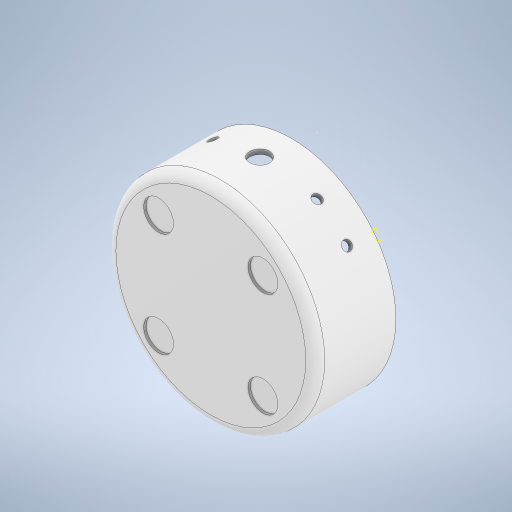
# Autodesk Inventor part: Основание
Saved by Autodesk Inventor 2024 (Build 280153000, 153)
## iProperties
Created: 2026-03-25
Part Number: Основание
Material: Типовые
Document SubType Name: Modeling
Designer: Pavel
Density: 1 g/cm^3
Appearance: По умолчанию
Author: Pavel
Autodesk Inventor part; units mm, degrees
ref_plane "РабПлоскость1" through (46.7801, -28.1809, 1.4774) normal (0.0000001, -1, 0) x (1, 0.0000001, 0.0000001)
ref_plane "РабПлоскость2" through (51.3477, 48.0491, 0.6174) normal (-0.0000001, 1, 0) x (-1, -0.0000001, 0)
sketch "Эскиз1" plane through (51.3477, 48.0491, 0.6174) normal (-0.0000001, 1, 0) x (-1, -0.0000001, 0)
  line L0 (0, 0) -> (2.8, 0) projected
  line L1 (0, -1.3) -> (0, 0) projected
  line L2 (2.8, -1.3) -> (0, -1.3) projected
  line L3 (2.8, 0) -> (2.8, -1.3) projected
  point P0 (51.3477, -0.6174)
sketch "Эскиз2" plane through (46.7801, -28.1809, 1.4774) normal (0.0000001, -1, 0) x (1, 0.0000001, 0.0000001)
  line L0 (6.3492, 0) -> (0, 0) projected
  arc A0 (7.4946, -1.2954) -> (6.3492, -0.15) centre (6.3492, -1.2954) ccw projected
  arc A1 (7.6446, -1.2954) -> (6.3492, 0) centre (6.3492, -1.2954) ccw projected
  arc A2 (6.3492, -3.16) -> (7.6446, -1.8646) centre (6.3492, -1.8646) ccw projected
  line L1 (7.6446, -1.8646) -> (7.6446, -1.2954) projected
  line L2 (2.6871, -3.16) -> (6.3492, -3.16) projected
  line L3 (0, -3.16) -> (2.6371, -3.16) projected
  arc A3 (-1.2954, -1.8646) -> (0, -3.16) centre (0, -1.8646) ccw projected
  arc A4 (0, 0) -> (-1.2954, -1.2954) centre (0, -1.2954) ccw projected
  line L4 (-1.2954, -1.2954) -> (-1.2954, -1.8646) projected
  line L5 (0, 0) -> (6.3492, 0)
  line L6 (6.3492, -3.16) -> (0, -3.16)
  arc A5 (-1.2954, -1.8646) -> (0, -3.16) centre (0, -1.8646) ccw
  arc A6 (0, 0) -> (-1.2954, -1.2954) centre (0, -1.2954) ccw
  arc A7 (7.6446, -1.2954) -> (6.3492, 0) centre (6.3492, -1.2954) ccw
  arc A8 (6.3492, -3.16) -> (7.6446, -1.8646) centre (6.3492, -1.8646) ccw
  line L7 (-1.2954, -1.2954) -> (-1.2954, -1.8646)
  line L8 (7.6446, -1.2954) -> (7.6446, -1.8646)
  arc A9 (7.6446, -1.2954) -> (6.3492, 0) centre (6.3492, -1.2954) ccw projected
  line L9 (7.6446, -1.8646) -> (7.6446, -1.2954) projected
  arc A10 (6.3492, -3.16) -> (7.6446, -1.8646) centre (6.3492, -1.8646) ccw projected
  line L10 (2.6871, -3.16) -> (6.3492, -3.16) projected
  line L11 (6.3492, 0) -> (0, 0) projected
  arc A11 (0, 0) -> (-1.2954, -1.2954) centre (0, -1.2954) ccw projected
  line L12 (-1.2954, -1.2954) -> (-1.2954, -1.8646) projected
  arc A12 (-1.2954, -1.8646) -> (0, -3.16) centre (0, -1.8646) ccw projected
  line L13 (0, -3.41) -> (6.3492, -3.41)
  arc A13 (6.3492, -3.41) -> (7.8946, -1.8646) centre (6.3492, -1.8646) ccw
  line L14 (7.8946, -1.8646) -> (7.8946, -1.2954)
  arc A14 (7.8946, -1.2954) -> (6.3492, 0.25) centre (6.3492, -1.2954) ccw
  line L15 (6.3492, 0.25) -> (0, 0.25)
  arc A15 (0, 0.25) -> (-1.5454, -1.2954) centre (0, -1.2954) ccw
  line L16 (-1.5454, -1.2954) -> (-1.5454, -1.8646)
  arc A16 (-1.5454, -1.8646) -> (0, -3.41) centre (0, -1.8646) ccw
  point P0 (-46.7801, -1.4774)
  dimension "d20" = 0.25
  constraints: 16 end point, 16 point on circle, 8 centre point, 4 coincident, 2 collinear, 2 parallel, 1 vertical, 7 other
  measures "d20" distance between parallel lines of L6 L13
ref_plane "РабПлоскость3" through (49.9497, 17.7991, -1.7826) normal (0, 0, 1) x (1, 0, 0)
ref_plane "РабПлоскость4" through (39.6247, 34.8888, -1.2881) normal (-0.5, 0.8660254, 0) x (-0.8660254, -0.5, 0)
ref_plane "РабПлоскость5" through (64.632, 43.9707, -1.7881) normal (0.5000001, 0.8660254, 0) x (-0.8660254, 0.5000001, 0)
sketch "Эскиз5" plane through (64.632, 43.9707, -1.7881) normal (0.5000001, 0.8660254, 0) x (-0.8660254, 0.5000001, 0)
  line L0 (-0.5, 1) -> (0, 1) projected
  line L1 (-1.25, 1) -> (-0.5, 1) projected
  line L2 (0, 1) -> (0.75, 1) projected
  circle A0 centre (-0.25, 0.5) radius 1
  point P0 (33.9877, 1.7881)
  constraints: 1 centre point, 1 coincident
ref_plane "РабПлоскость6" through (73.2116, 36.8036, -1.2881) normal (0.777146, 0.6293203, 0) x (-0.6293203, 0.777146, 0)
sketch "Эскиз6" plane through (73.2116, 36.8036, -1.2881) normal (0.777146, 0.6293203, 0) x (-0.6293203, 0.777146, 0)
  point P0 (17.4718, 1.2881)
ref_plane "РабПлоскость7" through (49.9497, 17.7991, -1.7826) normal (0, 0, 1) x (1, 0, 0)
sketch "Эскиз8" plane through (49.9497, 17.7991, -1.7826) normal (0, 0, 1) x (1, 0, 0)
  circle A0 centre (0, 0) radius 20 projected
  circle A1 centre (0, 0) radius 21
  circle A2 centre (0, 0) radius 22
  point P0 (-49.9497, -17.7991)
  dimension "d8" = 1
  dimension "d9" = 1
  constraints: 2 centre point
  measures "d8" radial gap between concentric circles of A0 A1
  measures "d9" radial gap between concentric circles of A1 A2
extrude "Выдавливание2" add sketch "Эскиз8" along normal blind 15 and the other way blind 5 contours A2
extrude "Выдавливание5" cut sketch "Эскиз1" against normal blind 15
extrude "Выдавливание7" cut sketch "Эскиз2" against normal blind 30 contours A1 L1 A2 L2 L6 L3 A3 L4 A4 L0 | A16 L16 A15 L15 A14 L14 A13 L13
sketch "Эскиз9" plane through (49.9497, 17.7991, 13.2174) normal (0, 0, 1) x (1, 0, 0)
  circle A0 centre (0, 0) radius 20 projected
  circle A1 centre (0, 0) radius 21 projected
  point P0 (-49.9497, -17.7991)
extrude "Выдавливание8" add sketch "Эскиз9" against normal blind 11
ref_plane "РабПлоскость8" through (49.9497, 17.7991, -1.7826) normal (0, 0, 1) x (1, 0, 0)
sketch "Эскиз10" plane through (49.9497, 17.7991, -1.7826) normal (0, 0, 1) x (1, 0, 0)
  circle A0 centre (-14, 11) radius 1 projected
  circle A1 centre (15, -9) radius 1 projected
  circle A2 centre (0, 0) radius 20 projected
  line L0 (16, -7.3333) -> (18.0687, -8.5745)
  line L1 (14, -10.6667) -> (16.0687, -11.9079)
  arc A3 (16, -7.3333) -> (14, -10.6667) centre (15, -9) ccw
  line L2 (15.8575, -9.5145) -> (14.4855, -9.8575)
  line L3 (14.4855, -9.8575) -> (14.1425, -8.4855)
  line L4 (14.1425, -8.4855) -> (15.5145, -8.1425)
  line L5 (15.5145, -8.1425) -> (15.8575, -9.5145)
  arc A4 (16.0687, -11.9079) -> (18.0687, -8.5745) centre (0, 0) ccw
  line L6 (-14, 11) -> (-15.7264, 12.3564)
  line L7 (-14.7863, 11.6178) -> (-13.3822, 11.7863)
  line L8 (-13.3822, 11.7863) -> (-13.2137, 10.3822)
  line L9 (-13.2137, 10.3822) -> (-14.6178, 10.2137)
  line L10 (-14.6178, 10.2137) -> (-14.7863, 11.6178)
  line L11 (-15.3956, 9.5409) -> (-16.8883, 10.7137)
  line L12 (-12.7644, 12.5726) -> (-14.4119, 13.8671)
  arc A5 (-15.3956, 9.5409) -> (-12.7644, 12.5726) centre (-14.154, 11.121) ccw
  arc A6 (-14.4119, 13.8671) -> (-16.8883, 10.7137) centre (0, 0) ccw
  line L13 (15, -9) -> (17.1499, -10.2899)
  line L14 (15, -9) -> (16.029, -7.285)
  line L15 (15, -9) -> (13.971, -10.715)
  arc A7 (16.0687, -11.9079) -> (18.0687, -8.5745) centre (0, 0) ccw
  point P0 (-49.9497, -17.7991)
  dimension "d31" = 2.0096
  dimension "d32" = 2
  dimension "d33" = 2
  constraints: 32 end point, 16 point on circle, 6 coincident, 5 centre point, 4 parallel, 2 line through centre, 2 perpendicular, 2 point on line, 13 other
  measures "d31" radius of A5
  measures "d32" distance of L13.start L14.end
  measures "d33" distance of L13.start L15.end
extrude "Выдавливание9" add sketch "Эскиз10" along normal up to surface (15 mm away) contours A0 L8 | L7 A0 | A0 L9 | L10 A0 | A1 L5 | A1 L14 L0 A2 L13 | L4 A1 | A1 L15 A3 L14 | L13 A2 L1 L15 A1 | A1 L2 | L3 A1 | A2 L12 A5 L11
sketch "Эскиз11" plane through (51.3477, 48.0491, 0.6174) normal (-0.0000001, 1, 0) x (-1, -0.0000001, 0)
  line L0 (2.8, -1.3) -> (2.8, 0) projected
  line L1 (0, 0) -> (2.8, 0) projected
  line L2 (2.8, -1.3) -> (0, 0)
  line L3 (2.8, 0) -> (0, -1.3)
  circle A0 centre (1.4, -0.65) radius 2.1
  point P0 (51.3477, -0.6174)
  dimension "d36" = 4.2
  constraints: 4 end point, 1 centre point, 1 midpoint
  measures "d36" diameter of A0
extrude "Выдавливание10" cut sketch "Эскиз11" against normal blind 10
sketch "Эскиз12" plane through (73.2116, 36.8036, -1.2881) normal (0.777146, 0.6293203, 0) x (-0.6293203, 0.777146, 0)
  circle A0 centre (-0.25, 0) radius 1
  point P0 (17.4718, 1.2881)
  constraints: 1 centre point
sketch "Эскиз14" plane through (49.9497, 17.7991, 13.2174) normal (0, 0, 1) x (1, 0, 0)
  circle A0 centre (0, 0) radius 22 projected
  point P0 (-49.9497, -17.7991)
extrude "Выдавливание12" cut sketch "Эскиз14" against normal blind 5
sketch "Эскиз15" plane through (49.9497, 17.7991, 2.2174) normal (0, 0, -1) x (-1, 0, 0)
  arc A0 (-16.0687, -11.9079) -> (16.8883, 10.7137) centre (0, 0) ccw projected
  line L0 (16.8883, 10.7137) -> (17.6785, 11.3346)
  circle A1 centre (0, 0) radius 21 projected
  arc A2 (14.4119, 13.8671) -> (-18.0687, -8.5745) centre (0, 0) ccw projected
  line L1 (14.4119, 13.8671) -> (15.202, 14.4879)
  line L2 (14.7863, 11.6178) -> (13.3822, 11.7863) projected
  line L3 (16.8883, 10.7137) -> (15.3956, 9.5409) projected
  arc A3 (16.8883, 10.7137) -> (14.4119, 13.8671) centre (0, 0) ccw projected
  arc A4 (16.8883, 10.7137) -> (14.4293, 13.849) centre (0, 0) ccw
  line L4 (-15.5145, -8.1425) -> (-15.8575, -9.5145) projected
  line L5 (-18.0687, -8.5745) -> (-18.9301, -9.0914)
  line L6 (-16.0687, -11.9079) -> (-16.9301, -12.4247)
  arc A5 (-18.0687, -8.5745) -> (-16.0687, -11.9079) centre (0, 0) ccw
  arc A6 (-18.9301, -9.0914) -> (-16.9301, -12.4247) centre (0, 0) ccw
  arc A7 (17.6785, 11.3346) -> (15.202, 14.4879) centre (0, 0) ccw
  point P0 (49.9497, -17.7991)
  constraints: 13 point on circle, 8 end point, 4 centre point, 4 coincident
extrude "Выдавливание13" add sketch "Эскиз15" along normal up to surface (4 mm away) contours L6 A1 L5 A5 | A3 L1 A1 L0
sketch "Эскиз16" plane through (49.9497, 17.7991, 8.2174) normal (0, 0, 1) x (1, 0, 0)
  circle A0 centre (0, 0) radius 22 projected
  point P0 (-49.9497, -17.7991)
extrude "Выдавливание14" add sketch "Эскиз16" along normal blind 2
fillet "Сопряжение2" radius 2 1 edges at (27.9497, 17.7991, 10.2174)
extrude "Выдавливание15" cut sketch "Эскиз12" against normal up to surface (10 mm away)
extrude "Выдавливание16" cut sketch "Эскиз5" against normal blind 10
ref_plane "РабПлоскость9" through (36.4497, 40.388, -1.2881) normal (-0.5, 0.8660254, 0) x (-0.8660254, -0.5, 0)
sketch "Эскиз17" plane through (36.4497, 40.388, -1.2881) normal (-0.5, 0.8660254, 0) x (-0.8660254, -0.5, 0)
  line L0 (-0.5, 0.5) -> (0, 0.5) projected
  circle A0 centre (-0.3141, 0.0002) radius 1
  point P0 (51.7604, 1.2881)
  constraints: 1 centre point
extrude "Выдавливание17" cut sketch "Эскиз17" against normal blind 10
sketch "Эскиз20" plane through (49.9497, 17.7991, -1.7826) normal (0, 0, -1) x (-1, 0, 0)
  line L0 (13.2137, 10.3822) -> (14.6178, 10.2137) projected
  line L1 (14.6178, 10.2137) -> (14.7863, 11.6178) projected
  line L2 (14.7863, 11.6178) -> (13.3822, 11.7863) projected
  line L3 (13.3822, 11.7863) -> (13.2137, 10.3822) projected
  line L4 (-14.4855, -9.8575) -> (-14.1425, -8.4855) projected
  line L5 (-14.1425, -8.4855) -> (-15.5145, -8.1425) projected
  line L6 (-15.5145, -8.1425) -> (-15.8575, -9.5145) projected
  line L7 (-15.8575, -9.5145) -> (-14.4855, -9.8575) projected
  point P0 (49.9497, -17.7991)
extrude "Выдавливание19" add sketch "Эскиз20" against normal blind 10
sketch "Эскиз21" plane through (49.9497, 17.7991, -1.7826) normal (0, 0, -1) x (-1, 0, 0)
  arc A0 (12.7644, 12.5726) -> (15.3956, 9.5409) centre (14.154, 11.121) ccw projected
  circle A1 centre (14.154, 11.121) radius 0.9
  arc A2 (-14, -10.6667) -> (-16, -7.3333) centre (-15, -9) ccw projected
  circle A3 centre (-15, -9) radius 0.9
  point P0 (49.9497, -17.7991)
  dimension "d62" = 1.8
  dimension "d63" = 1.8
  constraints: 2 centre point, 2 coincident
  measures "d62" diameter of A1
  measures "d63" diameter of A3
extrude "Выдавливание20" cut sketch "Эскиз21" against normal blind 10 contours A3
sketch "Эскиз22" plane through (49.9497, 17.7991, 10.2174) normal (0, 0, 1) x (1, 0, 0)
  circle A0 centre (-11, 11) radius 3.15
  circle A1 centre (11, 11) radius 3.15
  circle A2 centre (-11, -11) radius 3.15
  circle A3 centre (11, -11) radius 3.15
  line L0 (11, -11) -> (-11, -11)
  line L1 (-11, -11) -> (-11, 11)
  line L2 (-11, 11) -> (11, 11)
  line L3 (11, 11) -> (11, -11)
  line L4 (11, -11) -> (-11, 11) construction
  line L5 (-11, -11) -> (11, 11) construction
  point P0 (-49.9497, -17.7991)
  point P1 (0, 0)
  dimension "d72" = 6.3
  dimension "d73" = 6.3
  dimension "d74" = 6.3
  dimension "d75" = 6.3
  dimension "d78" = 22
  dimension "d79" = 22
  constraints: 12 end point, 4 centre point, 4 coincident, 2 midpoint, 2 parallel, 1 horizontal, 1 perpendicular
  measures "d72" diameter of A0
  measures "d73" diameter of A1
  measures "d74" diameter of A2
  measures "d75" diameter of A3
  measures "d78" distance of L1.end L2.end
  measures "d79" distance of L0.end L1.end
extrude "Выдавливание21" cut sketch "Эскиз22" against normal blind 0.5 contours L2 L1 A0 | A0 L1 L2 | L2 L3 A1 | A1 L3 L2 | L1 L0 A2 | A2 L0 L1 | L3 L0 A3 | A3 L0 L3
sketch "Эскиз23" plane through (49.9497, 17.7991, -1.7826) normal (0, 0, -1) x (-1, 0, 0)
  line L0 (0, 22) -> (31.4126, 22)
  line L1 (0, -22) -> (34.7387, -22)
  line L2 (0, 0) -> (14, 0)
  line L3 (14, 0) -> (14, 11)
  circle A0 centre (14, 11) radius 0.9
  line L4 (0, 0) -> (0, -9)
  point P0 (49.9497, -17.7991)
  dimension "d80" = 14
  dimension "d81" = 11
  dimension "d82" = 1.8
  constraints: 10 end point, 3 horizontal, 2 vertical, 1 centre point, 1 coincident
  measures "d80" distance of L2.start L2.end
  measures "d81" distance of L2.end L3.end
  measures "d82" diameter of A0
extrude "Выдавливание22" cut sketch "Эскиз23" against normal blind 10
